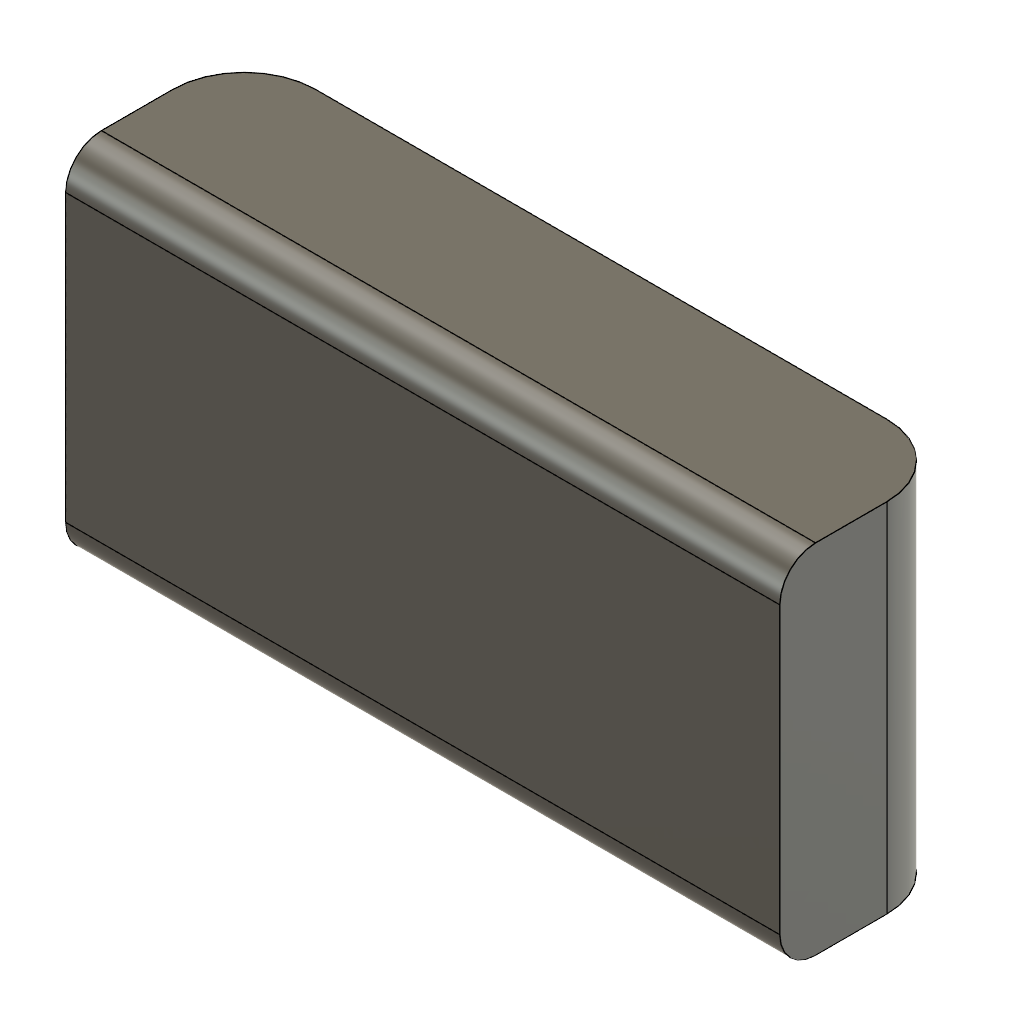
fillet_two_edge_sets (Autodesk Fusion 360 design; units mm, degrees)
part number: 2026-11-12-22-56-24-856
Autodesk Fusion 360 part; units mm, degrees
sketch "Sketch1" plane through (0, 0, 0) normal (0, 0, 1) x (1, 0, 0)
  line L0 (0, 0) -> (20, 0)
  line L1 (20, 0) -> (20, 10)
  line L2 (20, 10) -> (0, 10)
  line L3 (0, 10) -> (0, 0)
extrude "Extrude1" add sketch "Sketch1" along normal blind 5
fillet "Fillet1" radius 1 2 edges at (10, 0, 5) (10, 10, 5)
fillet "Fillet1" radius 2 2 edges at (0, 5, 0) (20, 5, 0)
